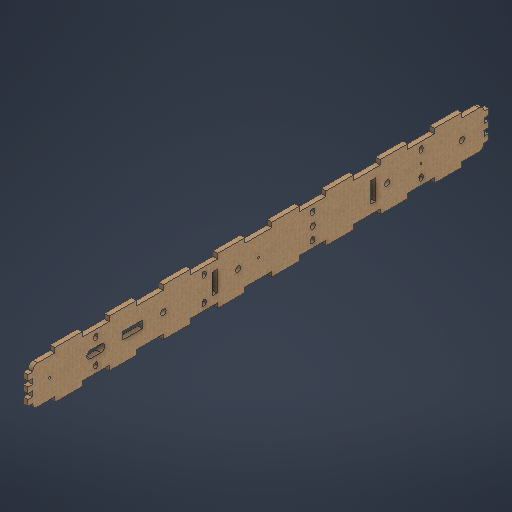
# Autodesk Inventor part: BaseBoxWidthFace
Saved by Autodesk Inventor 2027.1 (Build 311270010, 270A)
## iProperties
Created: 2026-10-13
Part Number: BaseBoxWidthFace
Material: MDF Medium Density Fiberboard
Document SubType Name: Modeling
Designer: SDS Scholar
Density: 0.8 g/cm^3
Appearance: Cardboard - Corrugated
Mass: 255.584 g
Surface Area: 1013.88 cm^2
Volume: 319.48 cm^3
Author: SDS Scholar
Autodesk Inventor part; units mm, degrees
ref_plane "YZ Plane" through (0, 0, 0) normal (1, 0, 0) x (0, 1, 0)
ref_plane "XZ Plane" through (0, 0, 0) normal (0, 1, 0) x (-1, 0, 0)
ref_plane "XY Plane" through (0, 0, 0) normal (0, 0, 1) x (1, 0, 0)
sketch "Sketch1" plane through (0, 0, 0) normal (1, 0, 0) x (0, 1, 0)
  line L0 (35, 340) -> (-35, 340)
  line L1 (-35, 340) -> (-35, -340)
  line L2 (-35, -340) -> (35, -340)
  line L3 (35, -340) -> (35, 340)
  point P0 (0, 0)
  point P1 (0, -340)
  point P2 (35, 0)
  dimension "d0" = 680
  dimension "d1" = 70
  constraints: 8 end point, 2 midpoint, 2 parallel, 1 horizontal, 1 horizontal alignment, 1 perpendicular, 1 vertical alignment
  measures "d0" distance of L2.end L0.start
  measures "d1" distance of L0.start L0.end
extrude "Extrusion1" add sketch "Sketch1" along normal blind 7
sketch "Sketch2" plane through (0, 0, 0) normal (-1, 0, 0) x (0, 0, 1)
  line L0 (247.7718, 0) -> (232.2282, 0) construction
  line L1 (247.7718, 5.5385) -> (232.2282, 5.5385)
  line L2 (232.2282, -5.5385) -> (247.7718, -5.5385)
  arc A0 (247.7718, -5.5385) -> (247.7718, 5.5385) centre (247.7718, 0) ccw
  arc A1 (232.2282, 5.5385) -> (232.2282, -5.5385) centre (232.2282, 0) ccw
  line L3 (340, 35) -> (340, -35) projected
  line L4 (340, 0) -> (240, 0) construction
  point P0 (0, 0)
  dimension "d4" = 100
  dimension "d5" = 15.5435
  dimension "d6" = 5.5385
  constraints: 10 end point, 4 point on circle, 4 tangent, 2 centre point, 2 midpoint, 1 collinear, 1 horizontal, 1 parallel
  measures "d4" distance from line of L3 L4.end
  measures "d5" distance of L2.start L2.end
  measures "d6" radius of A0
extrude "Extrusion2" cut sketch "Sketch2" against normal through all
sketch "Sketch3" plane through (7, 0, 0) normal (1, 0, 0) x (0, 0, -1)
  line L0 (-232.2282, -5.5385) -> (-247.7718, -5.5385) projected
  arc A0 (-247.7718, 5.5385) -> (-247.7718, -5.5385) centre (-247.7718, 0) ccw projected
  line L1 (-247.7718, 5.5385) -> (-232.2282, 5.5385) projected
  arc A1 (-232.2282, -5.5385) -> (-232.2282, 5.5385) centre (-232.2282, 0) ccw projected
  line L2 (-340, -35) -> (340, -35) projected
  line L3 (340, -35) -> (340, 35) projected
  line L4 (340, 35) -> (-340, 35) projected
  line L5 (-340, 35) -> (-340, -35) projected
  line L6 (-333, 28) -> (333, 28)
  line L7 (333, 28) -> (333, -28)
  line L8 (333, -28) -> (-333, -28)
  line L9 (-333, -28) -> (-333, 28)
  line L10 (-340, 35) -> (-300.225, 35)
  line L11 (-300.225, 35) -> (-300.225, 28)
  line L12 (-300.225, 28) -> (-340, 28)
  line L13 (-340, 28) -> (-340, 35)
  line L14 (-300.225, 35) -> (-259.775, 35)
  line L15 (-259.775, 35) -> (-259.775, 28)
  line L16 (-259.775, 28) -> (-300.225, 28)
  line L17 (-300.225, 28) -> (-300.225, 35)
  line L18 (-179.775, 35) -> (-179.775, 28)
  line L19 (-220.225, 35) -> (-220.225, 28)
  line L20 (-99.775, 35) -> (-99.775, 28)
  line L21 (-140.225, 35) -> (-140.225, 28)
  line L22 (-19.775, 35) -> (-19.775, 28)
  line L23 (-60.225, 35) -> (-60.225, 28)
  line L24 (60.225, 35) -> (60.225, 28)
  line L25 (19.775, 35) -> (19.775, 28)
  line L26 (140.225, 35) -> (140.225, 28)
  line L27 (99.775, 35) -> (99.775, 28)
  line L28 (220.225, 35) -> (220.225, 28)
  line L29 (179.775, 35) -> (179.775, 28)
  line L30 (300.225, 35) -> (300.225, 28)
  line L31 (259.775, 35) -> (259.775, 28)
  line L32 (-340, 0) -> (340, 0) construction
  line L33 (340, 35) -> (-340, 35) projected
  line L34 (0, 35) -> (0, -35) construction
  line L35 (-300.225, -35) -> (-300.225, -28)
  line L36 (-259.775, -35) -> (-259.775, -28)
  line L37 (-179.775, -35) -> (-179.775, -28)
  line L38 (-220.225, -35) -> (-220.225, -28)
  line L39 (-99.775, -35) -> (-99.775, -28)
  line L40 (-140.225, -35) -> (-140.225, -28)
  line L41 (-19.775, -35) -> (-19.775, -28)
  line L42 (-60.225, -35) -> (-60.225, -28)
  line L43 (60.225, -35) -> (60.225, -28)
  line L44 (19.775, -35) -> (19.775, -28)
  line L45 (140.225, -35) -> (140.225, -28)
  line L46 (99.775, -35) -> (99.775, -28)
  line L47 (220.225, -35) -> (220.225, -28)
  line L48 (179.775, -35) -> (179.775, -28)
  line L49 (300.225, -35) -> (300.225, -28)
  line L50 (259.775, -35) -> (259.775, -28)
  line L51 (0, -35) -> (0, 35) construction
  line L52 (-340, 28) -> (-333, 28)
  line L53 (-333, 28) -> (-333, 20.225)
  line L54 (-333, 20.225) -> (-340, 20.225)
  line L55 (-340, 20.225) -> (-340, 28)
  line L56 (-340, 20.225) -> (-333, 20.225)
  line L57 (-333, 20.225) -> (-333, 11.775)
  line L58 (-333, 11.775) -> (-340, 11.775)
  line L59 (-340, 11.775) -> (-340, 20.225)
  line L60 (-333, -28) -> (-340, -28)
  line L61 (-333, -4.225) -> (-340, -4.225)
  line L62 (-333, 4.225) -> (-340, 4.225)
  line L63 (-333, -20.225) -> (-340, -20.225)
  line L64 (-333, -11.775) -> (-340, -11.775)
  line L65 (300.225, 28) -> (340, 28)
  line L66 (333, 20.225) -> (340, 20.225)
  line L67 (333, 11.775) -> (340, 11.775)
  line L68 (333, -28) -> (340, -28)
  line L69 (333, -4.225) -> (340, -4.225)
  line L70 (333, 4.225) -> (340, 4.225)
  line L71 (333, -20.225) -> (340, -20.225)
  line L72 (333, -11.775) -> (340, -11.775)
  line L73 (-333, 28) -> (-333, 35)
  line L74 (-333, -28) -> (-333, -35)
  line L75 (333, 28) -> (333, 35)
  line L76 (333, -28) -> (333, -35)
  point P0 (0, 0)
  point P1 (333, -11.775)
  point P2 (333, -20.225)
  point P3 (333, -4.225)
  point P4 (333, 4.225)
  point P5 (333, 11.775)
  point P6 (333, 20.225)
  point P7 (-333, 4.225)
  point P8 (-333, -4.225)
  point P9 (-333, -11.775)
  point P10 (-333, -20.225)
  point P11 (-300.225, -35)
  point P12 (-300.225, -28)
  point P13 (-220.225, -35)
  point P14 (-220.225, -28)
  point P15 (-259.775, -28)
  point P16 (-259.775, -35)
  point P17 (-140.225, -35)
  point P18 (-140.225, -28)
  point P19 (-179.775, -28)
  point P20 (-179.775, -35)
  point P21 (-60.225, -35)
  point P22 (-60.225, -28)
  point P23 (-99.775, -28)
  point P24 (-99.775, -35)
  point P25 (19.775, -35)
  point P26 (19.775, -28)
  point P27 (-19.775, -28)
  point P28 (-19.775, -35)
  point P29 (99.775, -35)
  point P30 (99.775, -28)
  point P31 (60.225, -28)
  point P32 (60.225, -35)
  point P33 (179.775, -35)
  point P34 (179.775, -28)
  point P35 (140.225, -28)
  point P36 (140.225, -35)
  point P37 (220.225, -28)
  point P38 (300.225, -35)
  point P39 (300.225, 35)
  point P40 (300.225, 28)
  point P41 (259.775, 28)
  point P42 (259.775, 35)
  point P43 (220.225, 35)
  point P44 (220.225, 28)
  point P45 (179.775, 28)
  point P46 (179.775, 35)
  point P47 (140.225, 35)
  point P48 (140.225, 28)
  point P49 (99.775, 28)
  point P50 (99.775, 35)
  point P51 (60.225, 35)
  point P52 (60.225, 28)
  point P53 (19.775, 28)
  point P54 (19.775, 35)
  point P55 (-19.775, 35)
  point P56 (-19.775, 28)
  point P57 (-60.225, 28)
  point P58 (-60.225, 35)
  point P59 (-99.775, 35)
  point P60 (-99.775, 28)
  point P61 (-140.225, 28)
  point P62 (-140.225, 35)
  point P63 (-179.775, 35)
  point P64 (-179.775, 28)
  point P65 (-220.225, 28)
  point P66 (-220.225, 35)
  point P67 (-333, 28)
  point P68 (333, 28)
  point P69 (333, 35)
  point P70 (333, 28)
  point P71 (-333, 28)
  point P72 (-333, 35)
  dimension "d9" = 7
  dimension "d10" = 39.775
  dimension "d11" = 40.45
  dimension "d14" = 80
  dimension "d20" = 7.775
  dimension "d21" = 8.45
  dimension "d24" = 16
  constraints: 138 end point, 49 symmetric about line, 28 horizontal alignment, 23 parallel, 6 perpendicular, 5 point on line, 4 horizontal, 2 midpoint, 2 vertical, 28 other
  measures "d10" distance between parallel lines of L5 L11
  measures "d11" distance between parallel lines of L11 L15
  measures "d14" distance of L14.end L18.start
  measures "d20" distance between parallel lines of L12 L54
  measures "d21" distance between parallel lines of L56 L58
  measures "d24" distance of L57.end L61.start
extrude "Extrusion3" cut sketch "Sketch3" against normal through all contours L5 L60 L74 L2 | L74 L8 L35 L2 | L5 L63 L9 L60 | L36 L8 L38 L2 | L5 L61 L9 L64 | L37 L8 L40 L2 | L5 L58 L9 L62 | L39 L8 L42 L2 | L5 L12 L9 L54 | L5 L4 L73 L12 | L41 L8 L44 L2 | L73 L4 L11 L6 | L43 L8 L46 L2 | L15 L4 L19 L6 | L45 L8 L48 L2 | L18 L4 L21 L6 | L47 L8 L50 L2 | L20 L4 L23 L6 | L49 L8 L76 L2 | L22 L4 L25 L6 | L76 L68 L3 L2 | L7 L71 L3 L68 | L24 L4 L27 L6 | L7 L69 L3 L72 | L26 L4 L29 L6 | L7 L67 L3 L70 | L28 L4 L31 L6 | L7 L65 L3 L66 | L30 L4 L75 L6 | L75 L4 L3 L65
fillet "Fillet2" radius 7 4 edges at (3.5, 28, 333) (3.5, -28, 333) (3.5, 28, -333) (3.5, -28, -333)
sketch "Sketch5" plane through (0, 0, 0) normal (-1, 0, 0) x (0, 0, 1)
  line L0 (333, -21) -> (333, -20.225) projected
  line L1 (333, -20.225) -> (340, -20.225) projected
  line L2 (340, -11.775) -> (340, -20.225) projected
  line L3 (340, -11.775) -> (333, -11.775) projected
  line L4 (333, -11.775) -> (333, -4.225) projected
  line L5 (333, -4.225) -> (340, -4.225) projected
  line L6 (340, 4.225) -> (340, -4.225) projected
  line L7 (340, 4.225) -> (333, 4.225) projected
  line L8 (333, 4.225) -> (333, 11.775) projected
  line L9 (333, 11.775) -> (340, 11.775) projected
  line L10 (340, 20.225) -> (340, 11.775) projected
  line L11 (340, 20.225) -> (333, 20.225) projected
  line L12 (333, 20.225) -> (333, 21) projected
  line L13 (179.775, 35) -> (220.225, 35) projected
  line L14 (300.225, 28) -> (300.225, 35) projected
  line L15 (19.775, 28) -> (-19.775, 28) projected
  line L16 (259.775, 35) -> (259.775, 28) projected
  line L17 (-140.225, 35) -> (-99.775, 35) projected
  line L18 (220.225, 28) -> (220.225, 35) projected
  line L19 (-60.225, 28) -> (-99.775, 28) projected
  line L20 (179.775, 35) -> (179.775, 28) projected
  line L21 (-220.225, 35) -> (-179.775, 35) projected
  line L22 (140.225, 28) -> (140.225, 35) projected
  line L23 (-140.225, 28) -> (-179.775, 28) projected
  line L24 (99.775, 35) -> (99.775, 28) projected
  line L25 (99.775, 35) -> (140.225, 35) projected
  line L26 (60.225, 28) -> (60.225, 35) projected
  line L27 (-220.225, 28) -> (-259.775, 28) projected
  line L28 (19.775, 35) -> (19.775, 28) projected
  line L29 (259.775, 35) -> (300.225, 35) projected
  line L30 (-19.775, 28) -> (-19.775, 35) projected
  line L31 (-300.225, 28) -> (-326, 28) projected
  line L32 (-60.225, 35) -> (-60.225, 28) projected
  line L33 (-60.225, 35) -> (-19.775, 35) projected
  line L34 (-99.775, 28) -> (-99.775, 35) projected
  line L35 (259.775, 28) -> (220.225, 28) projected
  line L36 (-140.225, 35) -> (-140.225, 28) projected
  line L37 (-300.225, 35) -> (-259.775, 35) projected
  line L38 (-179.775, 28) -> (-179.775, 35) projected
  line L39 (179.775, 28) -> (140.225, 28) projected
  line L40 (-220.225, 35) -> (-220.225, 28) projected
  line L41 (19.775, 35) -> (60.225, 35) projected
  line L42 (-259.775, 28) -> (-259.775, 35) projected
  line L43 (326, 28) -> (300.225, 28) projected
  line L44 (-300.225, 35) -> (-300.225, 28) projected
  line L45 (-333, 21) -> (-333, 20.225) projected
  line L46 (-333, 20.225) -> (-340, 20.225) projected
  line L47 (-340, 11.775) -> (-340, 20.225) projected
  line L48 (-340, 11.775) -> (-333, 11.775) projected
  line L49 (-333, 11.775) -> (-333, 4.225) projected
  line L50 (-333, 4.225) -> (-340, 4.225) projected
  line L51 (-340, -4.225) -> (-340, 4.225) projected
  line L52 (-340, -4.225) -> (-333, -4.225) projected
  line L53 (-333, -4.225) -> (-333, -11.775) projected
  line L54 (-333, -11.775) -> (-340, -11.775) projected
  line L55 (-340, -20.225) -> (-340, -11.775) projected
  line L56 (-340, -20.225) -> (-333, -20.225) projected
  line L57 (-333, -20.225) -> (-333, -21) projected
  line L58 (-300.225, -28) -> (-300.225, -35) projected
  line L59 (-259.775, -28) -> (-220.225, -28) projected
  line L60 (-259.775, -35) -> (-259.775, -28) projected
  line L61 (-99.775, -35) -> (-140.225, -35) projected
  line L62 (-220.225, -28) -> (-220.225, -35) projected
  line L63 (-179.775, -28) -> (-140.225, -28) projected
  line L64 (-179.775, -35) -> (-179.775, -28) projected
  line L65 (220.225, -35) -> (179.775, -35) projected
  line L66 (-140.225, -28) -> (-140.225, -35) projected
  line L67 (-99.775, -28) -> (-60.225, -28) projected
  line L68 (-99.775, -35) -> (-99.775, -28) projected
  line L69 (300.225, -35) -> (259.775, -35) projected
  line L70 (-60.225, -28) -> (-60.225, -35) projected
  line L71 (-19.775, -28) -> (19.775, -28) projected
  line L72 (-19.775, -35) -> (-19.775, -28) projected
  line L73 (-19.775, -35) -> (-60.225, -35) projected
  line L74 (19.775, -28) -> (19.775, -35) projected
  line L75 (60.225, -28) -> (99.775, -28) projected
  line L76 (60.225, -35) -> (60.225, -28) projected
  line L77 (-179.775, -35) -> (-220.225, -35) projected
  line L78 (99.775, -28) -> (99.775, -35) projected
  line L79 (140.225, -28) -> (179.775, -28) projected
  line L80 (140.225, -35) -> (140.225, -28) projected
  line L81 (140.225, -35) -> (99.775, -35) projected
  line L82 (179.775, -28) -> (179.775, -35) projected
  line L83 (220.225, -28) -> (259.775, -28) projected
  line L84 (220.225, -35) -> (220.225, -28) projected
  line L85 (60.225, -35) -> (19.775, -35) projected
  line L86 (259.775, -28) -> (259.775, -35) projected
  line L87 (-326, -28) -> (-300.225, -28) projected
  line L88 (300.225, -35) -> (300.225, -28) projected
  line L89 (-259.775, -35) -> (-300.225, -35) projected
  line L90 (247.7718, -5.5385) -> (232.2282, -5.5385) projected
  arc A0 (232.2282, 5.5385) -> (232.2282, -5.5385) centre (232.2282, 0) ccw projected
  line L91 (232.2282, 5.5385) -> (247.7718, 5.5385) projected
  arc A1 (247.7718, -5.5385) -> (247.7718, 5.5385) centre (247.7718, 0) ccw projected
  line L92 (300.225, -28) -> (326, -28) projected
  line L93 (99.775, 28) -> (60.225, 28) projected
  arc A2 (-333, -21) -> (-326, -28) centre (-326, -21) ccw projected
  arc A3 (326, -28) -> (333, -21) centre (326, -21) ccw projected
  arc A4 (333, 21) -> (326, 28) centre (326, 21) ccw projected
  arc A5 (-326, 28) -> (-333, 21) centre (-326, 21) ccw projected
  line L94 (200, 5.5) -> (171, 5.5)
  line L95 (171, 5.5) -> (171, -5.5)
  line L96 (171, -5.5) -> (200, -5.5)
  line L97 (200, -5.5) -> (200, 5.5)
  line L98 (340, 4.225) -> (340, -4.225) projected
  circle A6 centre (-300, 0) radius 4
  circle A7 centre (-190, 0) radius 4
  circle A8 centre (-80, 0) radius 4
  circle A9 centre (30, 0) radius 4
  circle A10 centre (140, 0) radius 4
  circle A11 centre (250, 0) radius 4
  point P0 (0, 0)
  point P1 (-160, 28)
  point P2 (171, 0)
  point P3 (340, 0)
  point P4 (340, 0)
  point P5 (-340, 0)
  point P6 (252.1789, -3.3545)
  point P7 (252.1789, 3.3545)
  dimension "d62" = 11
  dimension "d63" = 29
  dimension "d64" = 140
  dimension "d65" = 8
  dimension "d68" = 40
  dimension "d71" = 110
  constraints: 8 end point, 6 centre point, 5 midpoint, 2 horizontal, 2 horizontal alignment, 2 parallel, 1 perpendicular, 10 other
  measures "d62" distance of L96.end L94.start
  measures "d63" distance of L95.end L96.end
  measures "d64" distance from line of point (340, 0) L97
  measures "d65" diameter of A6
  measures "d68" distance from line of L51 A6.centre
  measures "d71" distance of A6.centre A7.centre
extrude "Extrusion5" cut sketch "Sketch5" against normal through all contours A11 A1 | L97 L96 L95 L94 | A6 | A7 | A8 | A9 | A10 picked at (250.9792, -1.0095)
sketch "Sketch6" plane through (7, 0, 0) normal (1, 0, 0) x (0, 0, -1)
  line L0 (-300.225, -35) -> (-259.775, -35) projected
  line L1 (-300.225, -28) -> (-300.225, -35) projected
  line L2 (-259.775, -28) -> (-220.225, -28) projected
  line L3 (-259.775, -35) -> (-259.775, -28) projected
  line L4 (-220.225, -35) -> (-179.775, -35) projected
  line L5 (-220.225, -28) -> (-220.225, -35) projected
  line L6 (-179.775, -28) -> (-140.225, -28) projected
  line L7 (-179.775, -35) -> (-179.775, -28) projected
  line L8 (-140.225, -35) -> (-99.775, -35) projected
  line L9 (-140.225, -28) -> (-140.225, -35) projected
  line L10 (-99.775, -28) -> (-60.225, -28) projected
  line L11 (-99.775, -35) -> (-99.775, -28) projected
  line L12 (-60.225, -35) -> (-19.775, -35) projected
  line L13 (-60.225, -28) -> (-60.225, -35) projected
  line L14 (-19.775, -28) -> (19.775, -28) projected
  line L15 (-19.775, -35) -> (-19.775, -28) projected
  line L16 (19.775, -35) -> (60.225, -35) projected
  line L17 (19.775, -28) -> (19.775, -35) projected
  line L18 (60.225, -28) -> (99.775, -28) projected
  line L19 (60.225, -35) -> (60.225, -28) projected
  line L20 (99.775, -35) -> (140.225, -35) projected
  line L21 (99.775, -28) -> (99.775, -35) projected
  line L22 (140.225, -28) -> (179.775, -28) projected
  line L23 (140.225, -35) -> (140.225, -28) projected
  line L24 (179.775, -35) -> (220.225, -35) projected
  line L25 (179.775, -28) -> (179.775, -35) projected
  line L26 (220.225, -28) -> (259.775, -28) projected
  line L27 (220.225, -35) -> (220.225, -28) projected
  line L28 (259.775, -35) -> (300.225, -35) projected
  line L29 (259.775, -28) -> (259.775, -35) projected
  line L30 (-326, -28) -> (-300.225, -28) projected
  line L31 (300.225, -35) -> (300.225, -28) projected
  line L32 (333, -21) -> (333, -20.225) projected
  line L33 (333, -20.225) -> (340, -20.225) projected
  line L34 (340, -20.225) -> (340, -11.775) projected
  line L35 (340, -11.775) -> (333, -11.775) projected
  line L36 (333, -11.775) -> (333, -4.225) projected
  line L37 (333, -4.225) -> (340, -4.225) projected
  line L38 (340, -4.225) -> (340, 4.225) projected
  line L39 (340, 4.225) -> (333, 4.225) projected
  line L40 (333, 4.225) -> (333, 11.775) projected
  line L41 (333, 11.775) -> (340, 11.775) projected
  line L42 (340, 11.775) -> (340, 20.225) projected
  line L43 (340, 20.225) -> (333, 20.225) projected
  line L44 (333, 20.225) -> (333, 21) projected
  line L45 (300.225, 28) -> (300.225, 35) projected
  line L46 (-60.225, 28) -> (-99.775, 28) projected
  line L47 (259.775, 35) -> (259.775, 28) projected
  line L48 (300.225, 35) -> (259.775, 35) projected
  line L49 (220.225, 28) -> (220.225, 35) projected
  line L50 (-140.225, 28) -> (-179.775, 28) projected
  line L51 (179.775, 35) -> (179.775, 28) projected
  line L52 (220.225, 35) -> (179.775, 35) projected
  line L53 (140.225, 28) -> (140.225, 35) projected
  line L54 (-220.225, 28) -> (-259.775, 28) projected
  line L55 (99.775, 35) -> (99.775, 28) projected
  line L56 (140.225, 35) -> (99.775, 35) projected
  line L57 (60.225, 28) -> (60.225, 35) projected
  line L58 (-300.225, 28) -> (-326, 28) projected
  line L59 (19.775, 35) -> (19.775, 28) projected
  line L60 (60.225, 35) -> (19.775, 35) projected
  line L61 (-19.775, 28) -> (-19.775, 35) projected
  line L62 (259.775, 28) -> (220.225, 28) projected
  line L63 (-60.225, 35) -> (-60.225, 28) projected
  line L64 (-19.775, 35) -> (-60.225, 35) projected
  line L65 (-99.775, 28) -> (-99.775, 35) projected
  line L66 (179.775, 28) -> (140.225, 28) projected
  line L67 (-140.225, 35) -> (-140.225, 28) projected
  line L68 (-99.775, 35) -> (-140.225, 35) projected
  line L69 (-179.775, 28) -> (-179.775, 35) projected
  line L70 (99.775, 28) -> (60.225, 28) projected
  line L71 (-220.225, 35) -> (-220.225, 28) projected
  line L72 (-179.775, 35) -> (-220.225, 35) projected
  line L73 (-259.775, 28) -> (-259.775, 35) projected
  line L74 (326, 28) -> (300.225, 28) projected
  line L75 (-300.225, 35) -> (-300.225, 28) projected
  line L76 (-259.775, 35) -> (-300.225, 35) projected
  line L77 (-333, 21) -> (-333, 20.225) projected
  line L78 (-333, 20.225) -> (-340, 20.225) projected
  line L79 (-340, 20.225) -> (-340, 11.775) projected
  line L80 (-340, 11.775) -> (-333, 11.775) projected
  line L81 (-333, 11.775) -> (-333, 4.225) projected
  line L82 (-333, 4.225) -> (-340, 4.225) projected
  line L83 (-340, 4.225) -> (-340, -4.225) projected
  line L84 (-340, -4.225) -> (-333, -4.225) projected
  line L85 (-333, -4.225) -> (-333, -11.775) projected
  line L86 (-333, -11.775) -> (-340, -11.775) projected
  line L87 (-340, -11.775) -> (-340, -20.225) projected
  line L88 (-340, -20.225) -> (-333, -20.225) projected
  line L89 (-333, -20.225) -> (-333, -21) projected
  line L90 (-232.2282, -5.5385) -> (-247.7718, -5.5385) projected
  arc A0 (-247.7718, 5.5385) -> (-247.7718, -5.5385) centre (-247.7718, 0) ccw projected
  line L91 (-247.7718, 5.5385) -> (-232.2282, 5.5385) projected
  arc A1 (-232.2282, -5.5385) -> (-232.2282, 5.5385) centre (-232.2282, 0) ccw projected
  line L92 (173, -28) -> (173, 28)
  line L93 (166, 28) -> (166, -28)
  line L94 (166, 15) -> (173, 15)
  line L95 (173, 15) -> (173, -15)
  line L96 (173, -15) -> (166, -15)
  line L97 (166, -15) -> (166, 15)
  line L98 (-68, -28) -> (-68, 28)
  line L99 (-61, 28) -> (-61, -28)
  line L100 (-68, 15) -> (-61, 15)
  line L101 (-61, 15) -> (-61, -15)
  line L102 (-61, -15) -> (-68, -15)
  line L103 (-68, -15) -> (-68, 15)
  line L104 (300.225, -28) -> (326, -28) projected
  line L105 (19.775, 28) -> (-19.775, 28) projected
  arc A2 (326, -28) -> (333, -21) centre (326, -21) ccw projected
  arc A3 (333, 21) -> (326, 28) centre (326, 21) ccw projected
  arc A4 (-326, 28) -> (-333, 21) centre (-326, 21) ccw projected
  arc A5 (-333, -21) -> (-326, -28) centre (-326, -21) ccw projected
  point P0 (0, 0)
  point P1 (173, 0)
  point P2 (173, 0)
  point P3 (-61, 0)
  point P4 (-61, 0)
  dimension "d42" = 7
  dimension "d43" = 30
  dimension "d45" = 7
  dimension "d46" = 30
  dimension "d60" = 265
  dimension "d61" = 160
  constraints: 24 end point, 8 point on line, 4 midpoint, 4 parallel, 3 perpendicular, 2 coincident, 2 horizontal, 1 vertical
  measures "d42" distance between parallel lines of L92 L93
  measures "d43" distance of L94.end L95.end
  measures "d45" distance between parallel lines of L98 L99
  measures "d46" distance of L100.end L101.end
  measures "d60" distance between parallel lines of L103 L85
  measures "d61" distance between parallel lines of L36 L92
extrude "Extrusion6" cut sketch "Sketch6" against normal through all contours L98 L100 L99 L102 | L93 L94 L92 L96
sketch "Sketch7" plane through (7, 0, 0) normal (1, 0, 0) x (0, 0, -1)
  line L0 (19.775, 28) -> (-19.775, 28) projected
  line L1 (-19.775, -28) -> (19.775, -28) projected
  line L2 (340, -4.225) -> (340, 4.225) projected
  line L3 (-340, 4.225) -> (-340, -4.225) projected
  line L4 (-340, 0) -> (340, 0) construction
  line L5 (0, -28) -> (0, 28) construction
  line L6 (240, 16.5) -> (240, 19.5) construction
  line L7 (242.9, 16.5) -> (242.9, 19.5)
  line L8 (237.1, 19.5) -> (237.1, 16.5)
  arc A0 (237.1, 16.5) -> (242.9, 16.5) centre (240, 16.5) ccw
  arc A1 (242.9, 19.5) -> (237.1, 19.5) centre (240, 19.5) ccw
  line L9 (259.775, 28) -> (220.225, 28) projected
  line L10 (333, 4.225) -> (333, 11.775) projected
  line L11 (80, 16.5) -> (80, 19.5) construction
  line L12 (82.9, 16.5) -> (82.9, 19.5)
  line L13 (77.1, 19.5) -> (77.1, 16.5)
  arc A2 (77.1, 16.5) -> (82.9, 16.5) centre (80, 16.5) ccw
  arc A3 (82.9, 19.5) -> (77.1, 19.5) centre (80, 19.5) ccw
  line L14 (99.775, 28) -> (60.225, 28) projected
  line L15 (-240, 16.5) -> (-240, 19.5) construction
  line L16 (-242.9, 16.5) -> (-242.9, 19.5)
  line L17 (-237.1, 19.5) -> (-237.1, 16.5)
  arc A4 (-242.9, 16.5) -> (-237.1, 16.5) centre (-240, 16.5) ccw
  arc A5 (-237.1, 19.5) -> (-242.9, 19.5) centre (-240, 19.5) ccw
  line L18 (-80, 16.5) -> (-80, 19.5) construction
  line L19 (-82.9, 16.5) -> (-82.9, 19.5)
  line L20 (-77.1, 19.5) -> (-77.1, 16.5)
  arc A6 (-82.9, 16.5) -> (-77.1, 16.5) centre (-80, 16.5) ccw
  arc A7 (-77.1, 19.5) -> (-82.9, 19.5) centre (-80, 19.5) ccw
  line L21 (240, -16.5) -> (240, -19.5) construction
  line L22 (242.9, -16.5) -> (242.9, -19.5)
  line L23 (237.1, -19.5) -> (237.1, -16.5)
  arc A8 (242.9, -16.5) -> (237.1, -16.5) centre (240, -16.5) ccw
  arc A9 (237.1, -19.5) -> (242.9, -19.5) centre (240, -19.5) ccw
  line L24 (80, -16.5) -> (80, -19.5) construction
  line L25 (82.9, -16.5) -> (82.9, -19.5)
  line L26 (77.1, -19.5) -> (77.1, -16.5)
  arc A10 (82.9, -16.5) -> (77.1, -16.5) centre (80, -16.5) ccw
  arc A11 (77.1, -19.5) -> (82.9, -19.5) centre (80, -19.5) ccw
  line L27 (-82.9, -16.5) -> (-82.9, -19.5)
  arc A12 (-77.1, -16.5) -> (-82.9, -16.5) centre (-80, -16.5) ccw
  line L28 (-77.1, -19.5) -> (-77.1, -16.5)
  arc A13 (-82.9, -19.5) -> (-77.1, -19.5) centre (-80, -19.5) ccw
  line L29 (-80, -16.5) -> (-80, -19.5) construction
  line L30 (-242.9, -16.5) -> (-242.9, -19.5)
  line L31 (-240, -16.5) -> (-240, -19.5) construction
  arc A14 (-237.1, -16.5) -> (-242.9, -16.5) centre (-240, -16.5) ccw
  line L32 (-237.1, -19.5) -> (-237.1, -16.5)
  arc A15 (-242.9, -19.5) -> (-237.1, -19.5) centre (-240, -19.5) ccw
  line L33 (340, 11.775) -> (340, 20.225) projected
  point P0 (0, 0)
  point P1 (240, 18)
  point P2 (80, 18)
  point P3 (-240, 18)
  point P4 (-80, 18)
  point P5 (240, -18)
  point P6 (80, -18)
  point P7 (-80, -18)
  point P8 (-240, -18)
  dimension "d49" = 3
  dimension "d50" = 5.8
  dimension "d51" = 8.5
  dimension "d53" = 3
  dimension "d54" = 5.8
  dimension "d55" = 8.5
  dimension "d56" = 160
  dimension "d59" = 100
  constraints: 68 end point, 42 symmetric about line, 32 point on circle, 16 centre point, 8 tangent, 6 midpoint, 2 parallel, 1 perpendicular, 1 vertical, 12 other
  measures "d49" distance of L6.start L6.end
  measures "d50" diameter of A1
  measures "d51" distance from line of L9 L6.end
  measures "d53" distance of L11.start L11.end
  measures "d54" diameter of A3
  measures "d55" distance from line of L14 L11.end
  measures "d56" distance between parallel lines of L6 L11
  measures "d59" distance between parallel lines of L6 L33
extrude "Extrusion7" cut sketch "Sketch7" against normal through all
sketch "Sketch8" plane through (0, 0, 0) normal (-1, 0, 0) x (0, 0, 1)
  circle A0 centre (308, 0) radius 1.5
  line L0 (333, 4.225) -> (333, 11.775) projected
  circle A1 centre (0, 0) radius 1.5
  circle A2 centre (-240, 0) radius 1.5
  line L1 (-220.225, 28) -> (-259.775, 28) projected
  line L2 (-340, -4.225) -> (-340, 4.225) projected
  line L3 (340, 4.225) -> (340, -4.225) projected
  point P0 (-240, 28)
  point P1 (-340, 0)
  point P2 (340, 0)
  dimension "d76" = 3
  dimension "d77" = 25
  dimension "d78" = 3
  dimension "d79" = 3
  constraints: 3 centre point, 3 midpoint, 2 horizontal alignment, 1 coincident, 1 vertical alignment
  measures "d76" diameter of A0
  measures "d77" distance from line of L0 A0.centre
  measures "d78" diameter of A1
  measures "d79" diameter of A2
extrude "Extrusion8" cut sketch "Sketch8" against normal through all
equation "\"d0\" = BaseTotalWidth"
equation "\"d1\" = BaseHeight"
equation "\"d2\" = BaseWoodThickness"
equation "\"d9\" = BaseWoodThickness"
equation "\"d42\" = BaseWoodThickness"
equation "\"d45\" = BaseWoodThickness"
equation "\"GridProcutClearance\" = 5"
equation "\"GridBorderThickness\" = 5"
equation "\"GridBorderFillets\" = 7"
equation "\"GridTotalSize\" = 65"
equation "\"GridRobotClearance\" = 65"
equation "\"AluminiumExtrusionClearance\" = 35"
equation "\"BaseTotalWidth\" = 680"
equation "\"BaseTotalLength\" = 885"
equation "\"WorkspaceLength\" = 515"
equation "\"WorkspaceHeight\" = 183"
equation "\"AxesBaseFillet\" = 15"
equation "\"Zaxis\" = 197"
equation "\"ProductTotalHeight\" = 45"
equation "\"VerticalStroke\" = 105"
equation "\"BackArea\" = 165"
equation "\"CylinderStroke\" = 75"
equation "\"BaseHeight\" = 70"
equation "\"BoxesWidth\" = 125"
equation "\"BaseWoodThickness\" = 7"
equation "\"kerf\" = 1.5"
equation "\"Kerf\" = 0.3"
equation "\"RxThickness\" = 1.8"
equation "\"support_2\" = 265"
body "Solid1"
